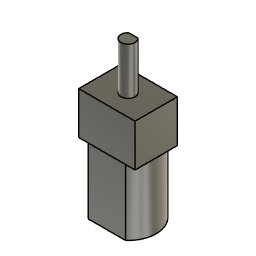
N20减速电机 v2 (Autodesk Fusion 360 design; units mm, degrees)
Autodesk Fusion 360 part; units mm, degrees
sketch "草图2" plane through (0, 0, 0) normal (0, 0, 1) x (1, 0, 0)
  circle A0 centre (0, 0) radius 1.5
  line L0 (0, 1.12) -> (-0.9978, 1.12)
  line L1 (0, 1.12) -> (0.9978, 1.12)
  dimension "d8" = 3
  dimension "d9" = 1.12
  constraint coincident A0.centre origin
  constraint coincident A0 L0.end
  constraint coincident A0 L1.end
  measures "d8" diameter of A0
  measures "d9" distance of A0.centre L0.start
extrude "拉伸1" add sketch "草图2" along normal blind 10 contours A0 L0 L1 picked at (0.0212, -0.6237) makes body 1
extrude "拉伸2" add sketch "草图2" along normal blind 3 separate body contours A0 L0 L1 picked at (-0.0725, 1.368) makes body 2
sketch "草图4" plane through (0, 0, 0) normal (0, 0, 1) x (1, 0, 0)
  line L0 (-6, 0) -> (-6, -4.5)
  line L1 (-6, -4.5) -> (6, -4.5)
  line L2 (6, -4.5) -> (6, 4.5)
  line L3 (6, 4.5) -> (-6, 4.5)
  line L4 (-6, 4.5) -> (-6, 0)
  dimension "d14" = 6
  dimension "d15" = 4.5
  dimension "d16" = 12
  dimension "d17" = 9
  dimension "d18" = 12
  constraint perpendicular L0 L1
  constraint perpendicular L1 L2
  constraint perpendicular L2 L3
  measures "d14" distance of origin L0.start
  measures "d15" distance of L0.start L0.end
  measures "d16" distance of L0.end L1.end
  measures "d17" distance of L1.end L2.end
  measures "d18" distance of L2.end L3.end
extrude "拉伸3" add sketch "草图4" against normal blind 9 separate body makes body 3
sketch "草图6" plane through (0, 0, -9) normal (0, 0, -1) x (1, 0, 0)
  line L0 (-6, 4.5) -> (-6, -4.5)
  line L1 (-6, -4.5) -> (6, -4.5)
  line L2 (6, -4.5) -> (6, 4.5)
  line L3 (6, 4.5) -> (-6, 4.5)
  line L4 (0, -4.5) -> (0, -4.75)
  line L5 (0, -4.75) -> (3.6657, -4.75)
  line L6 (0, -4.75) -> (-3.6657, -4.75)
  line L7 (0, 4.5) -> (0, 4.75)
  line L8 (0, 4.75) -> (3.6657, 4.75)
  line L9 (0, 4.75) -> (-3.6657, 4.75)
  arc A0 (3.6657, -4.75) -> (3.6657, 4.75) centre (0, 0) ccw
  arc A1 (-3.6657, 4.75) -> (-3.6657, -4.75) centre (0, 0) ccw
  dimension "d21" = 12
  dimension "d22" = 4.75
  dimension "d23" = 4.75
  constraint coincident A0.centre A1.centre
  constraint perpendicular L1 L4
  constraint perpendicular L4 L5
  constraint perpendicular L4 L6
  constraint parallel L4 L7
  constraint perpendicular L7 L8
  constraint coincident L9.end A0
  constraint perpendicular L7 L9
  constraint coincident L1 L4.start
  constraint coincident L3 L7.start
  constraint concentric A0 A1
  measures "d21" diameter of A0
  measures "d22" distance of A0.centre L4.end
  measures "d23" distance of A0.centre L7.end
extrude "拉伸4" add sketch "草图6" along normal blind 14 separate body contours L1 L3 A0 A1 makes body 4
equation "d22 = ( 9.5 / 2 ) * 1 mm"
